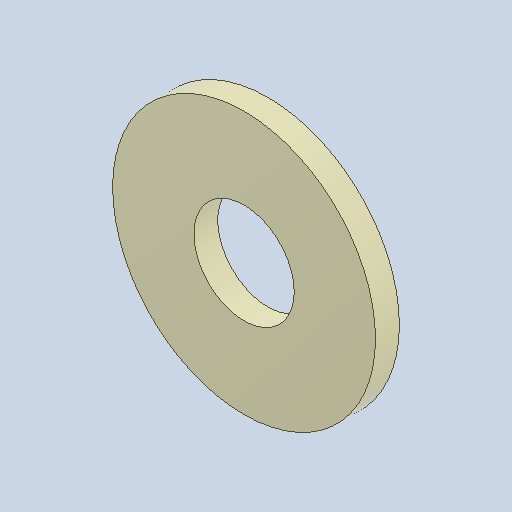
# Autodesk Inventor part: RDS-1105 Outlet Flange PP
Saved by Autodesk Inventor 2026.2 (Build 302298000, 298)
## iProperties
Created: 2026-10-18
Part Number: RDS-1105 Outlet Flange PP
Material: Polypropylene
Description: Outlet flange PP, placeholder
Document SubType Name: Modeling
Designer: admin
Stock Number: Фланец патрубка ПП (размер уточнить)
Density: 0.899 g/cm^3
Appearance: Smooth - Ash
Author: admin
Autodesk Inventor part; units mm, degrees
ref_plane "YZ Plane" through (0, 0, 0) normal (1, 0, 0) x (0, 1, 0)
ref_plane "XZ Plane" through (0, 0, 0) normal (0, 1, 0) x (-1, 0, 0)
ref_plane "XY Plane" through (0, 0, 0) normal (0, 0, 1) x (1, 0, 0)
sketch "Sketch1" plane through (0, 0, 0) normal (0, 0, 1) x (1, 0, 0)
  circle A0 centre (0, 0) radius 82.5
  circle A1 centre (0, 0) radius 31.5
  dimension "d0" = 165
  dimension "d1" = 63
  constraints: 2 centre point
  measures "d0" diameter of A0
  measures "d1" diameter of A1
extrude "Extrusion1" add sketch "Sketch1" along normal blind 15
equation "\"d0\" = Flange1105_Outer_Diam"
equation "\"d1\" = Flange1105_Inner_Diam"
equation "\"d2\" = Flange1105_Length"
equation "\"Flange1105_Outer_Diam\" = 165"
equation "\"Flange1105_Inner_Diam\" = 63"
equation "\"Flange1105_Length\" = 15"
body "Solid1"
